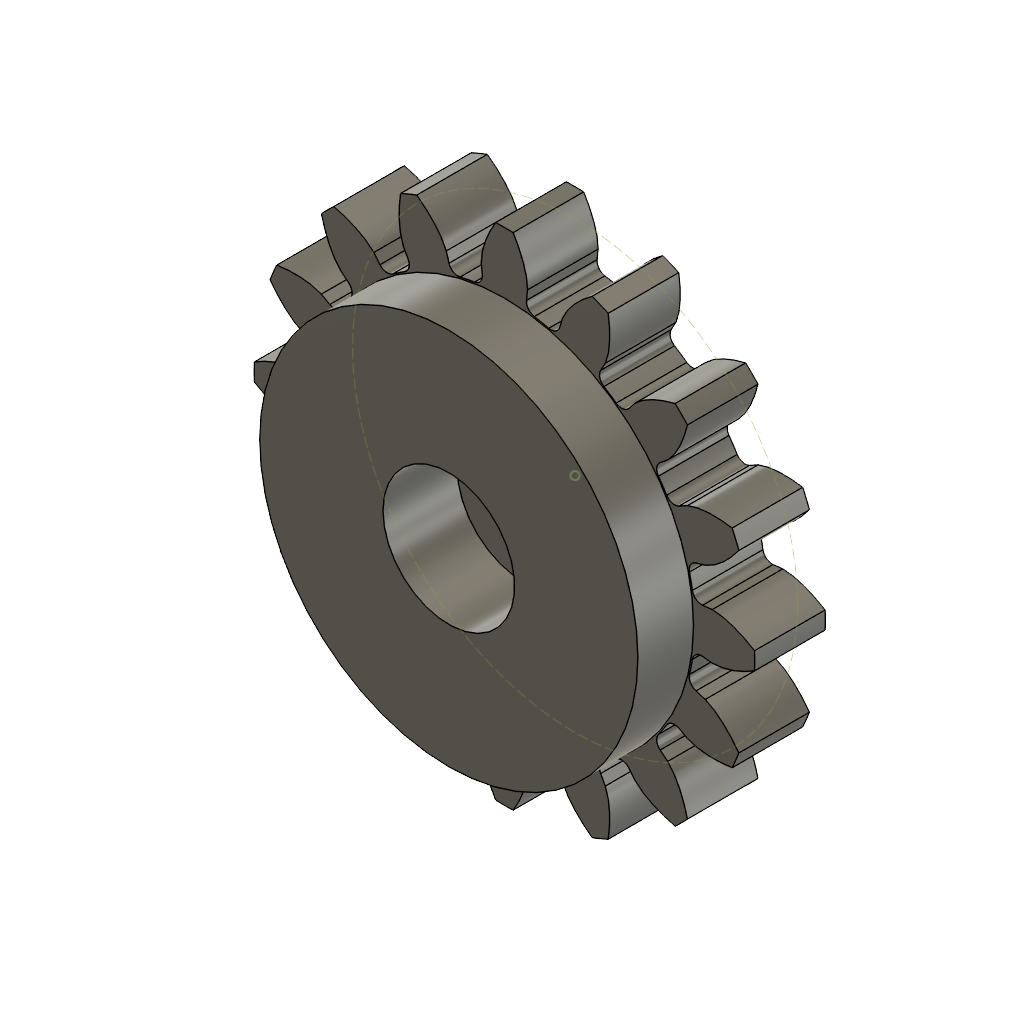
SpurGear (Autodesk Fusion 360 design; units mm, degrees)
part number: 2026-10-06-11-43-39-479
Autodesk Fusion 360 part; units mm, degrees
(part 1 of 6)
sketch "スケッチ1" plane through (0, 0, 0) normal (0, 0, 1) x (1, 0, 0)
  circle A0 centre (0, 0) radius 10.2645
extrude "押し出し1" add sketch "スケッチ1" along normal blind 3.81
sketch "スケッチ2" plane through (0, 0, 0) normal (0, 0, 1) x (1, 0, 0)
  spline S0 degree 5 poles (11.2069, -1.2491) (11.2134, -1.2498) (11.2264, -1.251) (11.246, -1.2524) (11.2721, -1.2531) (11.3048, -1.2525) (11.3376, -1.2509) (11.3704, -1.2487) (11.4033, -1.2461) (11.4361, -1.2432) (11.469, -1.2401) (11.502, -1.2367) (11.5349, -1.2328) (11.5679, -1.2284) (11.6008, -1.2235) (11.6338, -1.2181) (11.6668, -1.2124) (11.6998, -1.2062) (11.7328, -1.1998) (11.7659, -1.1931) (11.7989, -1.1861) (11.8319, -1.1788) (11.8649, -1.1712) (11.8979, -1.1632) (11.9309, -1.155) (11.9639, -1.1464) (11.9969, -1.1375) (12.0299, -1.1284) (12.0629, -1.119) (12.0958, -1.1093) (12.1288, -1.0993) (12.1617, -1.0891) (12.1947, -1.0787) (12.2276, -1.0679) (12.2605, -1.0569) (12.2934, -1.0457) (12.3262, -1.0342) (12.3591, -1.0224) (12.3919, -1.0105) (12.4247, -0.9982) (12.4575, -0.9858) (12.4903, -0.973) (12.5231, -0.9601) (12.5558, -0.9469) (12.5885, -0.9335) (12.6212, -0.9199) (12.6539, -0.906) (12.6865, -0.8919) (12.7191, -0.8776) (12.7517, -0.8631) (12.7842, -0.8483) (12.8167, -0.8334) (12.8492, -0.8182) (12.8817, -0.8028) (12.9141, -0.7872) (12.9465, -0.7713) (12.9789, -0.7553) (13.0112, -0.7391) (13.0435, -0.7226) (13.0758, -0.7059) (13.108, -0.6891) (13.1402, -0.672) (13.1724, -0.6547) (13.2045, -0.6373) (13.2366, -0.6196) (13.2686, -0.6017) (13.3006, -0.5836) (13.3326, -0.5654) (13.3645, -0.5469) (13.3964, -0.5282) (13.4282, -0.5094) (13.4537, -0.4942) (13.4727, -0.4826) (13.4854, -0.4749) (13.4918, -0.4711) knots 0 0 0 0 0 0 0.01428571 0.02857143 0.04285714 0.05714286 0.07142857 0.08571429 0.1 0.11428571 0.12857143 0.14285714 0.15714286 0.17142857 0.18571429 0.2 0.21428571 0.22857143 0.24285714 0.25714286 0.27142857 0.28571429 0.3 0.31428571 0.32857143 0.34285714 0.35714286 0.37142857 0.38571429 0.4 0.41428571 0.42857143 0.44285714 0.45714286 0.47142857 0.48571429 0.5 0.51428571 0.52857143 0.54285714 0.55714286 0.57142857 0.58571429 0.6 0.61428571 0.62857143 0.64285714 0.65714286 0.67142857 0.68571429 0.7 0.71428571 0.72857143 0.74285714 0.75714286 0.77142857 0.78571429 0.8 0.81428571 0.82857143 0.84285714 0.85714286 0.87142857 0.88571429 0.9 0.91428571 0.92857143 0.94285714 0.95714286 0.97142857 0.98571429 1 1 1 1 1 1
  spline S1 degree 5 poles (11.2069, 1.2491) (11.2134, 1.2498) (11.2264, 1.251) (11.246, 1.2524) (11.2721, 1.2531) (11.3048, 1.2525) (11.3376, 1.2509) (11.3704, 1.2487) (11.4033, 1.2461) (11.4361, 1.2432) (11.469, 1.2401) (11.502, 1.2367) (11.5349, 1.2328) (11.5679, 1.2284) (11.6008, 1.2235) (11.6338, 1.2181) (11.6668, 1.2124) (11.6998, 1.2062) (11.7328, 1.1998) (11.7659, 1.1931) (11.7989, 1.1861) (11.8319, 1.1788) (11.8649, 1.1712) (11.8979, 1.1632) (11.9309, 1.155) (11.9639, 1.1464) (11.9969, 1.1375) (12.0299, 1.1284) (12.0629, 1.119) (12.0958, 1.1093) (12.1288, 1.0993) (12.1617, 1.0891) (12.1947, 1.0787) (12.2276, 1.0679) (12.2605, 1.0569) (12.2934, 1.0457) (12.3262, 1.0342) (12.3591, 1.0224) (12.3919, 1.0105) (12.4247, 0.9982) (12.4575, 0.9858) (12.4903, 0.973) (12.5231, 0.9601) (12.5558, 0.9469) (12.5885, 0.9335) (12.6212, 0.9199) (12.6539, 0.906) (12.6865, 0.8919) (12.7191, 0.8776) (12.7517, 0.8631) (12.7842, 0.8483) (12.8167, 0.8334) (12.8492, 0.8182) (12.8817, 0.8028) (12.9141, 0.7872) (12.9465, 0.7713) (12.9789, 0.7553) (13.0112, 0.7391) (13.0435, 0.7226) (13.0758, 0.7059) (13.108, 0.6891) (13.1402, 0.672) (13.1724, 0.6547) (13.2045, 0.6373) (13.2366, 0.6196) (13.2686, 0.6017) (13.3006, 0.5836) (13.3326, 0.5654) (13.3645, 0.5469) (13.3964, 0.5282) (13.4282, 0.5094) (13.4537, 0.4942) (13.4727, 0.4826) (13.4854, 0.4749) (13.4918, 0.4711) knots 0 0 0 0 0 0 0.01428571 0.02857143 0.04285714 0.05714286 0.07142857 0.08571429 0.1 0.11428571 0.12857143 0.14285714 0.15714286 0.17142857 0.18571429 0.2 0.21428571 0.22857143 0.24285714 0.25714286 0.27142857 0.28571429 0.3 0.31428571 0.32857143 0.34285714 0.35714286 0.37142857 0.38571429 0.4 0.41428571 0.42857143 0.44285714 0.45714286 0.47142857 0.48571429 0.5 0.51428571 0.52857143 0.54285714 0.55714286 0.57142857 0.58571429 0.6 0.61428571 0.62857143 0.64285714 0.65714286 0.67142857 0.68571429 0.7 0.71428571 0.72857143 0.74285714 0.75714286 0.77142857 0.78571429 0.8 0.81428571 0.82857143 0.84285714 0.85714286 0.87142857 0.88571429 0.9 0.91428571 0.92857143 0.94285714 0.95714286 0.97142857 0.98571429 1 1 1 1 1 1
  arc A0 (13.4918, -0.4711) -> (13.4918, 0.4711) centre (0, 0) ccw
  line L0 (10.1914, -1.1359) -> (11.2069, -1.2491)
  line L1 (10.1914, 1.1359) -> (11.2069, 1.2491)
  line L2 (10.1914, -1.1359) -> (10.1914, 1.1359)
  point P0 (11.3667, -1.2488)
  point P1 (11.5282, -1.2335)
  point P2 (11.6906, -1.2079)
  point P3 (11.8537, -1.1737)
  point P4 (12.0173, -1.1318)
  point P5 (12.1813, -1.0829)
  point P6 (12.3455, -1.0273)
  point P7 (12.5098, -0.9653)
  point P8 (12.6741, -0.8972)
  point P9 (12.8383, -0.8233)
  point P10 (13.0023, -0.7435)
  point P11 (13.1659, -0.6582)
  point P12 (13.3291, -0.5673)
  point P13 (11.3667, 1.2488)
  point P14 (11.5282, 1.2335)
  point P15 (11.6906, 1.2079)
  point P16 (11.8537, 1.1737)
  point P17 (12.0173, 1.1318)
  point P18 (12.1813, 1.0829)
  point P19 (12.3455, 1.0273)
  point P20 (12.5098, 0.9653)
  point P21 (12.6741, 0.8972)
  point P22 (12.8383, 0.8233)
  point P23 (13.0023, 0.7435)
  point P24 (13.1659, 0.6582)
  point P25 (13.3291, 0.5673)
extrude "押し出し2" add sketch "スケッチ2" along normal blind 3.81
fillet "フィレット1" radius 0.5 2 edges at (10.2013, -1.137, 1.905) (10.2013, 1.137, 1.905)
pattern_circular "C パターン1" count 16 over 360 about axis through (0, 0, 0) along (0, 0, 1) of "押し出し2", "フィレット1"
sketch "スケッチ3" plane through (0, 0, 0) normal (0, 0, 1) x (1, 0, 0)
  circle A0 centre (0, 0) radius 12 construction
sketch "スケッチ4" plane through (0, 0, 3.81) normal (0, 0, 1) x (1, 0, 0)
  arc A0 (9.9818, -2.3924) -> (10.1375, -1.6096) centre (0, 0) ccw
  arc A1 (10.6867, -1.1911) -> (10.1375, -1.6096) centre (10.6313, -1.688) ccw
  line L0 (10.6867, -1.1911) -> (11.2069, -1.2491)
  spline S0 degree 5 poles (11.2069, -1.2491) (11.2134, -1.2498) (11.2264, -1.251) (11.246, -1.2524) (11.2721, -1.2531) (11.3048, -1.2525) (11.3376, -1.2509) (11.3704, -1.2487) (11.4033, -1.2461) (11.4361, -1.2432) (11.469, -1.2401) (11.502, -1.2367) (11.5349, -1.2328) (11.5679, -1.2284) (11.6008, -1.2235) (11.6338, -1.2181) (11.6668, -1.2124) (11.6998, -1.2062) (11.7328, -1.1998) (11.7659, -1.1931) (11.7989, -1.1861) (11.8319, -1.1788) (11.8649, -1.1712) (11.8979, -1.1632) (11.9309, -1.155) (11.9639, -1.1464) (11.9969, -1.1375) (12.0299, -1.1284) (12.0629, -1.119) (12.0958, -1.1093) (12.1288, -1.0993) (12.1617, -1.0891) (12.1947, -1.0787) (12.2276, -1.0679) (12.2605, -1.0569) (12.2934, -1.0457) (12.3262, -1.0342) (12.3591, -1.0224) (12.3919, -1.0105) (12.4247, -0.9982) (12.4575, -0.9858) (12.4903, -0.973) (12.5231, -0.9601) (12.5558, -0.9469) (12.5885, -0.9335) (12.6212, -0.9199) (12.6539, -0.906) (12.6865, -0.8919) (12.7191, -0.8776) (12.7517, -0.8631) (12.7842, -0.8483) (12.8167, -0.8334) (12.8492, -0.8182) (12.8817, -0.8028) (12.9141, -0.7872) (12.9465, -0.7713) (12.9789, -0.7553) (13.0112, -0.7391) (13.0435, -0.7226) (13.0758, -0.7059) (13.108, -0.6891) (13.1402, -0.672) (13.1724, -0.6547) (13.2045, -0.6373) (13.2366, -0.6196) (13.2686, -0.6017) (13.3006, -0.5836) (13.3326, -0.5654) (13.3645, -0.5469) (13.3964, -0.5282) (13.4282, -0.5094) (13.4537, -0.4942) (13.4727, -0.4826) (13.4854, -0.4749) (13.4918, -0.4711) knots 0 0 0 0 0 0 0.01428571 0.02857143 0.04285714 0.05714286 0.07142857 0.08571429 0.1 0.11428571 0.12857143 0.14285714 0.15714286 0.17142857 0.18571429 0.2 0.21428571 0.22857143 0.24285714 0.25714286 0.27142857 0.28571429 0.3 0.31428571 0.32857143 0.34285714 0.35714286 0.37142857 0.38571429 0.4 0.41428571 0.42857143 0.44285714 0.45714286 0.47142857 0.48571429 0.5 0.51428571 0.52857143 0.54285714 0.55714286 0.57142857 0.58571429 0.6 0.61428571 0.62857143 0.64285714 0.65714286 0.67142857 0.68571429 0.7 0.71428571 0.72857143 0.74285714 0.75714286 0.77142857 0.78571429 0.8 0.81428571 0.82857143 0.84285714 0.85714286 0.87142857 0.88571429 0.9 0.91428571 0.92857143 0.94285714 0.95714286 0.97142857 0.98571429 1 1 1 1 1 1
  arc A2 (13.4918, -0.4711) -> (13.4918, 0.4711) centre (0, 0) ccw
  spline S1 degree 5 poles (13.4918, 0.4711) (13.4854, 0.4749) (13.4727, 0.4826) (13.4537, 0.4942) (13.4282, 0.5094) (13.3964, 0.5282) (13.3645, 0.5469) (13.3326, 0.5654) (13.3006, 0.5836) (13.2686, 0.6017) (13.2366, 0.6196) (13.2045, 0.6373) (13.1724, 0.6547) (13.1402, 0.672) (13.108, 0.6891) (13.0758, 0.7059) (13.0435, 0.7226) (13.0112, 0.7391) (12.9789, 0.7553) (12.9465, 0.7713) (12.9141, 0.7872) (12.8817, 0.8028) (12.8492, 0.8182) (12.8167, 0.8334) (12.7842, 0.8483) (12.7517, 0.8631) (12.7191, 0.8776) (12.6865, 0.8919) (12.6539, 0.906) (12.6212, 0.9199) (12.5885, 0.9335) (12.5558, 0.9469) (12.5231, 0.9601) (12.4903, 0.973) (12.4575, 0.9858) (12.4247, 0.9982) (12.3919, 1.0105) (12.3591, 1.0224) (12.3262, 1.0342) (12.2934, 1.0457) (12.2605, 1.0569) (12.2276, 1.0679) (12.1947, 1.0787) (12.1617, 1.0891) (12.1288, 1.0993) (12.0958, 1.1093) (12.0629, 1.119) (12.0299, 1.1284) (11.9969, 1.1375) (11.9639, 1.1464) (11.9309, 1.155) (11.8979, 1.1632) (11.8649, 1.1712) (11.8319, 1.1788) (11.7989, 1.1861) (11.7659, 1.1931) (11.7328, 1.1998) (11.6998, 1.2062) (11.6668, 1.2124) (11.6338, 1.2181) (11.6008, 1.2235) (11.5679, 1.2284) (11.5349, 1.2328) (11.502, 1.2367) (11.469, 1.2401) (11.4361, 1.2432) (11.4033, 1.2461) (11.3704, 1.2487) (11.3376, 1.2509) (11.3048, 1.2525) (11.2721, 1.2531) (11.246, 1.2524) (11.2264, 1.251) (11.2134, 1.2498) (11.2069, 1.2491) knots -1 -1 -1 -1 -1 -1 -0.98571429 -0.97142857 -0.95714286 -0.94285714 -0.92857143 -0.91428571 -0.9 -0.88571429 -0.87142857 -0.85714286 -0.84285714 -0.82857143 -0.81428571 -0.8 -0.78571429 -0.77142857 -0.75714286 -0.74285714 -0.72857143 -0.71428571 -0.7 -0.68571429 -0.67142857 -0.65714286 -0.64285714 -0.62857143 -0.61428571 -0.6 -0.58571429 -0.57142857 -0.55714286 -0.54285714 -0.52857143 -0.51428571 -0.5 -0.48571429 -0.47142857 -0.45714286 -0.44285714 -0.42857143 -0.41428571 -0.4 -0.38571429 -0.37142857 -0.35714286 -0.34285714 -0.32857143 -0.31428571 -0.3 -0.28571429 -0.27142857 -0.25714286 -0.24285714 -0.22857143 -0.21428571 -0.2 -0.18571429 -0.17142857 -0.15714286 -0.14285714 -0.12857143 -0.11428571 -0.1 -0.08571429 -0.07142857 -0.05714286 -0.04285714 -0.02857143 -0.01428571 0 0 0 0 0 0
  line L1 (11.2069, 1.2491) -> (10.6867, 1.1911)
  arc A3 (10.1375, 1.6096) -> (10.6867, 1.1911) centre (10.6313, 1.688) ccw
  arc A4 (10.1375, 1.6096) -> (9.9818, 2.3924) centre (0, 0) ccw
  arc A5 (10.329, 2.9892) -> (9.9818, 2.3924) centre (10.468, 2.5089) ccw
  line L2 (10.329, 2.9892) -> (10.8318, 3.1347)
  spline S2 degree 5 poles (10.8318, 3.1347) (10.8381, 3.1365) (10.8506, 3.1404) (10.8692, 3.1466) (10.8936, 3.1559) (10.9236, 3.169) (10.9533, 3.183) (10.9827, 3.1976) (11.0121, 3.2126) (11.0414, 3.2279) (11.0706, 3.2433) (11.0997, 3.2591) (11.1286, 3.2753) (11.1574, 3.2919) (11.186, 3.3091) (11.2144, 3.3267) (11.2427, 3.3446) (11.2708, 3.3629) (11.2989, 3.3815) (11.3268, 3.4003) (11.3546, 3.4194) (11.3823, 3.4388) (11.4099, 3.4585) (11.4374, 3.4784) (11.4647, 3.4987) (11.4919, 3.5193) (11.519, 3.5401) (11.546, 3.5611) (11.5728, 3.5825) (11.5996, 3.604) (11.6262, 3.6258) (11.6528, 3.6479) (11.6792, 3.6701) (11.7055, 3.6926) (11.7317, 3.7154) (11.7578, 3.7384) (11.7837, 3.7616) (11.8096, 3.785) (11.8353, 3.8086) (11.861, 3.8325) (11.8865, 3.8566) (11.9119, 3.8809) (11.9372, 3.9054) (11.9624, 3.93) (11.9875, 3.955) (12.0125, 3.9801) (12.0374, 4.0054) (12.0621, 4.0309) (12.0868, 4.0566) (12.1113, 4.0825) (12.1357, 4.1085) (12.16, 4.1348) (12.1843, 4.1613) (12.2083, 4.1879) (12.2323, 4.2148) (12.2562, 4.2418) (12.28, 4.269) (12.3036, 4.2964) (12.3272, 4.3239) (12.3506, 4.3517) (12.3739, 4.3796) (12.3971, 4.4077) (12.4202, 4.4359) (12.4432, 4.4644) (12.4661, 4.493) (12.4889, 4.5218) (12.5115, 4.5507) (12.5341, 4.5798) (12.5565, 4.6091) (12.5788, 4.6385) (12.601, 4.6681) (12.6187, 4.692) (12.6319, 4.7099) (12.6407, 4.7219) (12.645, 4.7279) knots 0 0 0 0 0 0 0.01428571 0.02857143 0.04285714 0.05714286 0.07142857 0.08571429 0.1 0.11428571 0.12857143 0.14285714 0.15714286 0.17142857 0.18571429 0.2 0.21428571 0.22857143 0.24285714 0.25714286 0.27142857 0.28571429 0.3 0.31428571 0.32857143 0.34285714 0.35714286 0.37142857 0.38571429 0.4 0.41428571 0.42857143 0.44285714 0.45714286 0.47142857 0.48571429 0.5 0.51428571 0.52857143 0.54285714 0.55714286 0.57142857 0.58571429 0.6 0.61428571 0.62857143 0.64285714 0.65714286 0.67142857 0.68571429 0.7 0.71428571 0.72857143 0.74285714 0.75714286 0.77142857 0.78571429 0.8 0.81428571 0.82857143 0.84285714 0.85714286 0.87142857 0.88571429 0.9 0.91428571 0.92857143 0.94285714 0.95714286 0.97142857 0.98571429 1 1 1 1 1 1
  arc A6 (12.645, 4.7279) -> (12.2845, 5.5983) centre (0, 0) ccw
  spline S3 degree 5 poles (12.2845, 5.5983) (12.2772, 5.5994) (12.2625, 5.6017) (12.2405, 5.605) (12.2111, 5.6094) (12.1745, 5.6146) (12.1379, 5.6197) (12.1013, 5.6245) (12.0648, 5.6291) (12.0283, 5.6336) (11.9919, 5.6378) (11.9555, 5.6419) (11.9191, 5.6457) (11.8828, 5.6494) (11.8465, 5.6529) (11.8103, 5.6561) (11.7741, 5.6591) (11.738, 5.662) (11.7019, 5.6646) (11.6659, 5.6671) (11.6299, 5.6693) (11.5939, 5.6713) (11.558, 5.6731) (11.5222, 5.6747) (11.4864, 5.6761) (11.4507, 5.6772) (11.4151, 5.6782) (11.3795, 5.6789) (11.3439, 5.6795) (11.3084, 5.6798) (11.273, 5.6799) (11.2377, 5.6797) (11.2024, 5.6794) (11.1672, 5.6788) (11.132, 5.678) (11.097, 5.677) (11.062, 5.6757) (11.027, 5.6742) (10.9922, 5.6725) (10.9574, 5.6706) (10.9227, 5.6684) (10.8881, 5.6659) (10.8536, 5.6633) (10.8192, 5.6603) (10.7848, 5.6571) (10.7506, 5.6537) (10.7164, 5.6501) (10.6823, 5.6461) (10.6484, 5.642) (10.6145, 5.6375) (10.5807, 5.6328) (10.5471, 5.6278) (10.5135, 5.6225) (10.4801, 5.6169) (10.4468, 5.611) (10.4137, 5.6049) (10.3806, 5.5984) (10.3476, 5.5917) (10.3148, 5.5848) (10.2821, 5.5775) (10.2496, 5.5698) (10.2172, 5.5617) (10.1851, 5.5532) (10.1532, 5.5441) (10.1215, 5.5347) (10.0899, 5.525) (10.0584, 5.515) (10.027, 5.5049) (9.9958, 5.4944) (9.9649, 5.4833) (9.9345, 5.4713) (9.9106, 5.4607) (9.8931, 5.452) (9.8816, 5.4458) (9.8759, 5.4427) knots -1 -1 -1 -1 -1 -1 -0.98571429 -0.97142857 -0.95714286 -0.94285714 -0.92857143 -0.91428571 -0.9 -0.88571429 -0.87142857 -0.85714286 -0.84285714 -0.82857143 -0.81428571 -0.8 -0.78571429 -0.77142857 -0.75714286 -0.74285714 -0.72857143 -0.71428571 -0.7 -0.68571429 -0.67142857 -0.65714286 -0.64285714 -0.62857143 -0.61428571 -0.6 -0.58571429 -0.57142857 -0.55714286 -0.54285714 -0.52857143 -0.51428571 -0.5 -0.48571429 -0.47142857 -0.45714286 -0.44285714 -0.42857143 -0.41428571 -0.4 -0.38571429 -0.37142857 -0.35714286 -0.34285714 -0.32857143 -0.31428571 -0.3 -0.28571429 -0.27142857 -0.25714286 -0.24285714 -0.22857143 -0.21428571 -0.2 -0.18571429 -0.17142857 -0.15714286 -0.14285714 -0.12857143 -0.11428571 -0.1 -0.08571429 -0.07142857 -0.05714286 -0.04285714 -0.02857143 -0.01428571 0 0 0 0 0 0
  line L3 (9.8759, 5.4427) -> (9.4174, 5.19)
  arc A7 (8.7499, 5.3665) -> (9.4174, 5.19) centre (9.1761, 5.6279) ccw
  arc A8 (8.7499, 5.3665) -> (8.3065, 6.0302) centre (0, 0) ccw
  arc A9 (8.3989, 6.7144) -> (8.3065, 6.0302) centre (8.7111, 6.3239) ccw
  line L4 (8.3989, 6.7144) -> (8.8077, 7.0413)
  spline S4 degree 5 poles (8.8077, 7.0413) (8.8128, 7.0454) (8.8229, 7.0537) (8.8377, 7.0665) (8.8566, 7.0845) (8.8794, 7.108) (8.9014, 7.1323) (8.923, 7.1571) (8.9444, 7.1822) (8.9656, 7.2075) (8.9867, 7.233) (9.0076, 7.2587) (9.0281, 7.2847) (9.0483, 7.3111) (9.0682, 7.3379) (9.0877, 7.365) (9.107, 7.3924) (9.126, 7.4201) (9.1448, 7.448) (9.1634, 7.4761) (9.1817, 7.5044) (9.1999, 7.5329) (9.2179, 7.5616) (9.2356, 7.5906) (9.2531, 7.6197) (9.2704, 7.6491) (9.2874, 7.6787) (9.3043, 7.7085) (9.321, 7.7385) (9.3374, 7.7687) (9.3537, 7.799) (9.3698, 7.8295) (9.3857, 7.8602) (9.4013, 7.8911) (9.4168, 7.9221) (9.4321, 7.9533) (9.4473, 7.9847) (9.4622, 8.0162) (9.4769, 8.0479) (9.4915, 8.0798) (9.5058, 8.1118) (9.52, 8.1439) (9.534, 8.1763) (9.5479, 8.2087) (9.5615, 8.2413) (9.575, 8.2741) (9.5883, 8.307) (9.6014, 8.34) (9.6143, 8.3732) (9.6271, 8.4065) (9.6397, 8.4399) (9.6521, 8.4735) (9.6643, 8.5072) (9.6764, 8.5411) (9.6883, 8.5751) (9.7, 8.6092) (9.7115, 8.6434) (9.7229, 8.6777) (9.7341, 8.7122) (9.7452, 8.7468) (9.756, 8.7815) (9.7667, 8.8164) (9.7772, 8.8513) (9.7876, 8.8864) (9.7978, 8.9216) (9.8078, 8.9569) (9.8177, 8.9923) (9.8273, 9.0278) (9.8369, 9.0634) (9.8462, 9.0992) (9.8554, 9.135) (9.8626, 9.1638) (9.8679, 9.1854) (9.8715, 9.1998) (9.8732, 9.207) knots 0 0 0 0 0 0 0.01428571 0.02857143 0.04285714 0.05714286 0.07142857 0.08571429 0.1 0.11428571 0.12857143 0.14285714 0.15714286 0.17142857 0.18571429 0.2 0.21428571 0.22857143 0.24285714 0.25714286 0.27142857 0.28571429 0.3 0.31428571 0.32857143 0.34285714 0.35714286 0.37142857 0.38571429 0.4 0.41428571 0.42857143 0.44285714 0.45714286 0.47142857 0.48571429 0.5 0.51428571 0.52857143 0.54285714 0.55714286 0.57142857 0.58571429 0.6 0.61428571 0.62857143 0.64285714 0.65714286 0.67142857 0.68571429 0.7 0.71428571 0.72857143 0.74285714 0.75714286 0.77142857 0.78571429 0.8 0.81428571 0.82857143 0.84285714 0.85714286 0.87142857 0.88571429 0.9 0.91428571 0.92857143 0.94285714 0.95714286 0.97142857 0.98571429 1 1 1 1 1 1
  arc A10 (9.8732, 9.207) -> (9.207, 9.8732) centre (0, 0) ccw
  spline S5 degree 5 poles (9.207, 9.8732) (9.1998, 9.8715) (9.1854, 9.8679) (9.1638, 9.8626) (9.135, 9.8554) (9.0992, 9.8462) (9.0634, 9.8369) (9.0278, 9.8273) (8.9923, 9.8177) (8.9569, 9.8078) (8.9216, 9.7978) (8.8864, 9.7876) (8.8513, 9.7772) (8.8164, 9.7667) (8.7815, 9.756) (8.7468, 9.7452) (8.7122, 9.7341) (8.6777, 9.7229) (8.6434, 9.7115) (8.6092, 9.7) (8.5751, 9.6883) (8.5411, 9.6764) (8.5072, 9.6643) (8.4735, 9.6521) (8.4399, 9.6397) (8.4065, 9.6271) (8.3732, 9.6143) (8.34, 9.6014) (8.307, 9.5883) (8.2741, 9.575) (8.2413, 9.5615) (8.2087, 9.5479) (8.1763, 9.534) (8.1439, 9.52) (8.1118, 9.5058) (8.0798, 9.4915) (8.0479, 9.4769) (8.0162, 9.4622) (7.9847, 9.4473) (7.9533, 9.4321) (7.9221, 9.4168) (7.8911, 9.4013) (7.8602, 9.3857) (7.8295, 9.3698) (7.799, 9.3537) (7.7687, 9.3374) (7.7385, 9.321) (7.7085, 9.3043) (7.6787, 9.2874) (7.6491, 9.2704) (7.6197, 9.2531) (7.5906, 9.2356) (7.5616, 9.2179) (7.5329, 9.1999) (7.5044, 9.1817) (7.4761, 9.1634) (7.448, 9.1448) (7.4201, 9.126) (7.3924, 9.107) (7.365, 9.0877) (7.3379, 9.0682) (7.3111, 9.0483) (7.2847, 9.0281) (7.2587, 9.0076) (7.233, 8.9867) (7.2075, 8.9656) (7.1822, 8.9444) (7.1571, 8.923) (7.1323, 8.9014) (7.108, 8.8794) (7.0845, 8.8566) (7.0665, 8.8377) (7.0537, 8.8229) (7.0454, 8.8128) (7.0413, 8.8077) knots -1 -1 -1 -1 -1 -1 -0.98571429 -0.97142857 -0.95714286 -0.94285714 -0.92857143 -0.91428571 -0.9 -0.88571429 -0.87142857 -0.85714286 -0.84285714 -0.82857143 -0.81428571 -0.8 -0.78571429 -0.77142857 -0.75714286 -0.74285714 -0.72857143 -0.71428571 -0.7 -0.68571429 -0.67142857 -0.65714286 -0.64285714 -0.62857143 -0.61428571 -0.6 -0.58571429 -0.57142857 -0.55714286 -0.54285714 -0.52857143 -0.51428571 -0.5 -0.48571429 -0.47142857 -0.45714286 -0.44285714 -0.42857143 -0.41428571 -0.4 -0.38571429 -0.37142857 -0.35714286 -0.34285714 -0.32857143 -0.31428571 -0.3 -0.28571429 -0.27142857 -0.25714286 -0.24285714 -0.22857143 -0.21428571 -0.2 -0.18571429 -0.17142857 -0.15714286 -0.14285714 -0.12857143 -0.11428571 -0.1 -0.08571429 -0.07142857 -0.05714286 -0.04285714 -0.02857143 -0.01428571 0 0 0 0 0 0
  line L5 (7.0413, 8.8077) -> (6.7144, 8.3989)
  arc A11 (6.0302, 8.3065) -> (6.7144, 8.3989) centre (6.3239, 8.7111) ccw
  arc A12 (6.0302, 8.3065) -> (5.3665, 8.7499) centre (0, 0) ccw
  arc A13 (5.19, 9.4174) -> (5.3665, 8.7499) centre (5.6279, 9.1761) ccw
  line L6 (5.19, 9.4174) -> (5.4427, 9.8759)
  spline S6 degree 5 poles (5.4427, 9.8759) (5.4458, 9.8816) (5.452, 9.8931) (5.4607, 9.9106) (5.4713, 9.9345) (5.4833, 9.9649) (5.4944, 9.9958) (5.5049, 10.027) (5.515, 10.0584) (5.525, 10.0899) (5.5347, 10.1215) (5.5441, 10.1532) (5.5532, 10.1851) (5.5617, 10.2172) (5.5698, 10.2496) (5.5775, 10.2821) (5.5848, 10.3148) (5.5917, 10.3476) (5.5984, 10.3806) (5.6049, 10.4137) (5.611, 10.4468) (5.6169, 10.4801) (5.6225, 10.5135) (5.6278, 10.5471) (5.6328, 10.5807) (5.6375, 10.6145) (5.642, 10.6484) (5.6461, 10.6823) (5.6501, 10.7164) (5.6537, 10.7506) (5.6571, 10.7848) (5.6603, 10.8192) (5.6633, 10.8536) (5.6659, 10.8881) (5.6684, 10.9227) (5.6706, 10.9574) (5.6725, 10.9922) (5.6742, 11.027) (5.6757, 11.062) (5.677, 11.097) (5.678, 11.132) (5.6788, 11.1672) (5.6794, 11.2024) (5.6797, 11.2377) (5.6799, 11.273) (5.6798, 11.3084) (5.6795, 11.3439) (5.6789, 11.3795) (5.6782, 11.4151) (5.6772, 11.4507) (5.6761, 11.4864) (5.6747, 11.5222) (5.6731, 11.558) (5.6713, 11.5939) (5.6693, 11.6299) (5.6671, 11.6659) (5.6646, 11.7019) (5.662, 11.738) (5.6591, 11.7741) (5.6561, 11.8103) (5.6529, 11.8465) (5.6494, 11.8828) (5.6457, 11.9191) (5.6419, 11.9555) (5.6378, 11.9919) (5.6336, 12.0283) (5.6291, 12.0648) (5.6245, 12.1013) (5.6197, 12.1379) (5.6146, 12.1745) (5.6094, 12.2111) (5.605, 12.2405) (5.6017, 12.2625) (5.5994, 12.2772) (5.5983, 12.2845) knots 0 0 0 0 0 0 0.01428571 0.02857143 0.04285714 0.05714286 0.07142857 0.08571429 0.1 0.11428571 0.12857143 0.14285714 0.15714286 0.17142857 0.18571429 0.2 0.21428571 0.22857143 0.24285714 0.25714286 0.27142857 0.28571429 0.3 0.31428571 0.32857143 0.34285714 0.35714286 0.37142857 0.38571429 0.4 0.41428571 0.42857143 0.44285714 0.45714286 0.47142857 0.48571429 0.5 0.51428571 0.52857143 0.54285714 0.55714286 0.57142857 0.58571429 0.6 0.61428571 0.62857143 0.64285714 0.65714286 0.67142857 0.68571429 0.7 0.71428571 0.72857143 0.74285714 0.75714286 0.77142857 0.78571429 0.8 0.81428571 0.82857143 0.84285714 0.85714286 0.87142857 0.88571429 0.9 0.91428571 0.92857143 0.94285714 0.95714286 0.97142857 0.98571429 1 1 1 1 1 1
  arc A14 (5.5983, 12.2845) -> (4.7279, 12.645) centre (0, 0) ccw
  spline S7 degree 5 poles (4.7279, 12.645) (4.7219, 12.6407) (4.7099, 12.6319) (4.692, 12.6187) (4.6681, 12.601) (4.6385, 12.5788) (4.6091, 12.5565) (4.5798, 12.5341) (4.5507, 12.5115) (4.5218, 12.4889) (4.493, 12.4661) (4.4644, 12.4432) (4.4359, 12.4202) (4.4077, 12.3971) (4.3796, 12.3739) (4.3517, 12.3506) (4.3239, 12.3272) (4.2964, 12.3036) (4.269, 12.28) (4.2418, 12.2562) (4.2148, 12.2323) (4.1879, 12.2083) (4.1613, 12.1843) (4.1348, 12.16) (4.1085, 12.1357) (4.0825, 12.1113) (4.0566, 12.0868) (4.0309, 12.0621) (4.0054, 12.0374) (3.9801, 12.0125) (3.955, 11.9875) (3.93, 11.9624) (3.9054, 11.9372) (3.8809, 11.9119) (3.8566, 11.8865) (3.8325, 11.861) (3.8086, 11.8353) (3.785, 11.8096) (3.7616, 11.7837) (3.7384, 11.7578) (3.7154, 11.7317) (3.6926, 11.7055) (3.6701, 11.6792) (3.6479, 11.6528) (3.6258, 11.6262) (3.604, 11.5996) (3.5825, 11.5728) (3.5611, 11.546) (3.5401, 11.519) (3.5193, 11.4919) (3.4987, 11.4647) (3.4784, 11.4374) (3.4585, 11.4099) (3.4388, 11.3823) (3.4194, 11.3546) (3.4003, 11.3268) (3.3815, 11.2989) (3.3629, 11.2708) (3.3446, 11.2427) (3.3267, 11.2144) (3.3091, 11.186) (3.2919, 11.1574) (3.2753, 11.1286) (3.2591, 11.0997) (3.2433, 11.0706) (3.2279, 11.0414) (3.2126, 11.0121) (3.1976, 10.9827) (3.183, 10.9533) (3.169, 10.9236) (3.1559, 10.8936) (3.1466, 10.8692) (3.1404, 10.8506) (3.1365, 10.8381) (3.1347, 10.8318) knots -1 -1 -1 -1 -1 -1 -0.98571429 -0.97142857 -0.95714286 -0.94285714 -0.92857143 -0.91428571 -0.9 -0.88571429 -0.87142857 -0.85714286 -0.84285714 -0.82857143 -0.81428571 -0.8 -0.78571429 -0.77142857 -0.75714286 -0.74285714 -0.72857143 -0.71428571 -0.7 -0.68571429 -0.67142857 -0.65714286 -0.64285714 -0.62857143 -0.61428571 -0.6 -0.58571429 -0.57142857 -0.55714286 -0.54285714 -0.52857143 -0.51428571 -0.5 -0.48571429 -0.47142857 -0.45714286 -0.44285714 -0.42857143 -0.41428571 -0.4 -0.38571429 -0.37142857 -0.35714286 -0.34285714 -0.32857143 -0.31428571 -0.3 -0.28571429 -0.27142857 -0.25714286 -0.24285714 -0.22857143 -0.21428571 -0.2 -0.18571429 -0.17142857 -0.15714286 -0.14285714 -0.12857143 -0.11428571 -0.1 -0.08571429 -0.07142857 -0.05714286 -0.04285714 -0.02857143 -0.01428571 0 0 0 0 0 0
  line L7 (3.1347, 10.8318) -> (2.9892, 10.329)
  arc A15 (2.3924, 9.9818) -> (2.9892, 10.329) centre (2.5089, 10.468) ccw
  arc A16 (2.3924, 9.9818) -> (1.6096, 10.1375) centre (0, 0) ccw
  arc A17 (1.1911, 10.6867) -> (1.6096, 10.1375) centre (1.688, 10.6313) ccw
  line L8 (1.1911, 10.6867) -> (1.2491, 11.2069)
  spline S8 degree 5 poles (1.2491, 11.2069) (1.2498, 11.2134) (1.251, 11.2264) (1.2524, 11.246) (1.2531, 11.2721) (1.2525, 11.3048) (1.2509, 11.3376) (1.2487, 11.3704) (1.2461, 11.4033) (1.2432, 11.4361) (1.2401, 11.469) (1.2367, 11.502) (1.2328, 11.5349) (1.2284, 11.5679) (1.2235, 11.6008) (1.2181, 11.6338) (1.2124, 11.6668) (1.2062, 11.6998) (1.1998, 11.7328) (1.1931, 11.7659) (1.1861, 11.7989) (1.1788, 11.8319) (1.1712, 11.8649) (1.1632, 11.8979) (1.155, 11.9309) (1.1464, 11.9639) (1.1375, 11.9969) (1.1284, 12.0299) (1.119, 12.0629) (1.1093, 12.0958) (1.0993, 12.1288) (1.0891, 12.1617) (1.0787, 12.1947) (1.0679, 12.2276) (1.0569, 12.2605) (1.0457, 12.2934) (1.0342, 12.3262) (1.0224, 12.3591) (1.0105, 12.3919) (0.9982, 12.4247) (0.9858, 12.4575) (0.973, 12.4903) (0.9601, 12.5231) (0.9469, 12.5558) (0.9335, 12.5885) (0.9199, 12.6212) (0.906, 12.6539) (0.8919, 12.6865) (0.8776, 12.7191) (0.8631, 12.7517) (0.8483, 12.7842) (0.8334, 12.8167) (0.8182, 12.8492) (0.8028, 12.8817) (0.7872, 12.9141) (0.7713, 12.9465) (0.7553, 12.9789) (0.7391, 13.0112) (0.7226, 13.0435) (0.7059, 13.0758) (0.6891, 13.108) (0.672, 13.1402) (0.6547, 13.1724) (0.6373, 13.2045) (0.6196, 13.2366) (0.6017, 13.2686) (0.5836, 13.3006) (0.5654, 13.3326) (0.5469, 13.3645) (0.5282, 13.3964) (0.5094, 13.4282) (0.4942, 13.4537) (0.4826, 13.4727) (0.4749, 13.4854) (0.4711, 13.4918) knots 0 0 0 0 0 0 0.01428571 0.02857143 0.04285714 0.05714286 0.07142857 0.08571429 0.1 0.11428571 0.12857143 0.14285714 0.15714286 0.17142857 0.18571429 0.2 0.21428571 0.22857143 0.24285714 0.25714286 0.27142857 0.28571429 0.3 0.31428571 0.32857143 0.34285714 0.35714286 0.37142857 0.38571429 0.4 0.41428571 0.42857143 0.44285714 0.45714286 0.47142857 0.48571429 0.5 0.51428571 0.52857143 0.54285714 0.55714286 0.57142857 0.58571429 0.6 0.61428571 0.62857143 0.64285714 0.65714286 0.67142857 0.68571429 0.7 0.71428571 0.72857143 0.74285714 0.75714286 0.77142857 0.78571429 0.8 0.81428571 0.82857143 0.84285714 0.85714286 0.87142857 0.88571429 0.9 0.91428571 0.92857143 0.94285714 0.95714286 0.97142857 0.98571429 1 1 1 1 1 1
  arc A18 (0.4711, 13.4918) -> (-0.4711, 13.4918) centre (0, 0) ccw
  spline S9 degree 5 poles (-0.4711, 13.4918) (-0.4749, 13.4854) (-0.4826, 13.4727) (-0.4942, 13.4537) (-0.5094, 13.4282) (-0.5282, 13.3964) (-0.5469, 13.3645) (-0.5654, 13.3326) (-0.5836, 13.3006) (-0.6017, 13.2686) (-0.6196, 13.2366) (-0.6373, 13.2045) (-0.6547, 13.1724) (-0.672, 13.1402) (-0.6891, 13.108) (-0.7059, 13.0758) (-0.7226, 13.0435) (-0.7391, 13.0112) (-0.7553, 12.9789) (-0.7713, 12.9465) (-0.7872, 12.9141) (-0.8028, 12.8817) (-0.8182, 12.8492) (-0.8334, 12.8167) (-0.8483, 12.7842) (-0.8631, 12.7517) (-0.8776, 12.7191) (-0.8919, 12.6865) (-0.906, 12.6539) (-0.9199, 12.6212) (-0.9335, 12.5885) (-0.9469, 12.5558) (-0.9601, 12.5231) (-0.973, 12.4903) (-0.9858, 12.4575) (-0.9982, 12.4247) (-1.0105, 12.3919) (-1.0224, 12.3591) (-1.0342, 12.3262) (-1.0457, 12.2934) (-1.0569, 12.2605) (-1.0679, 12.2276) (-1.0787, 12.1947) (-1.0891, 12.1617) (-1.0993, 12.1288) (-1.1093, 12.0958) (-1.119, 12.0629) (-1.1284, 12.0299) (-1.1375, 11.9969) (-1.1464, 11.9639) (-1.155, 11.9309) (-1.1632, 11.8979) (-1.1712, 11.8649) (-1.1788, 11.8319) (-1.1861, 11.7989) (-1.1931, 11.7659) (-1.1998, 11.7328) (-1.2062, 11.6998) (-1.2124, 11.6668) (-1.2181, 11.6338) (-1.2235, 11.6008) (-1.2284, 11.5679) (-1.2328, 11.5349) (-1.2367, 11.502) (-1.2401, 11.469) (-1.2432, 11.4361) (-1.2461, 11.4033) (-1.2487, 11.3704) (-1.2509, 11.3376) (-1.2525, 11.3048) (-1.2531, 11.2721) (-1.2524, 11.246) (-1.251, 11.2264) (-1.2498, 11.2134) (-1.2491, 11.2069) knots -1 -1 -1 -1 -1 -1 -0.98571429 -0.97142857 -0.95714286 -0.94285714 -0.92857143 -0.91428571 -0.9 -0.88571429 -0.87142857 -0.85714286 -0.84285714 -0.82857143 -0.81428571 -0.8 -0.78571429 -0.77142857 -0.75714286 -0.74285714 -0.72857143 -0.71428571 -0.7 -0.68571429 -0.67142857 -0.65714286 -0.64285714 -0.62857143 -0.61428571 -0.6 -0.58571429 -0.57142857 -0.55714286 -0.54285714 -0.52857143 -0.51428571 -0.5 -0.48571429 -0.47142857 -0.45714286 -0.44285714 -0.42857143 -0.41428571 -0.4 -0.38571429 -0.37142857 -0.35714286 -0.34285714 -0.32857143 -0.31428571 -0.3 -0.28571429 -0.27142857 -0.25714286 -0.24285714 -0.22857143 -0.21428571 -0.2 -0.18571429 -0.17142857 -0.15714286 -0.14285714 -0.12857143 -0.11428571 -0.1 -0.08571429 -0.07142857 -0.05714286 -0.04285714 -0.02857143 -0.01428571 0 0 0 0 0 0
  line L9 (-1.2491, 11.2069) -> (-1.1911, 10.6867)
  arc A19 (-1.6096, 10.1375) -> (-1.1911, 10.6867) centre (-1.688, 10.6313) ccw
  arc A20 (-1.6096, 10.1375) -> (-2.3924, 9.9818) centre (0, 0) ccw
  arc A21 (-2.9892, 10.329) -> (-2.3924, 9.9818) centre (-2.5089, 10.468) ccw
  line L10 (-2.9892, 10.329) -> (-3.1347, 10.8318)
  spline S10 degree 5 poles (-3.1347, 10.8318) (-3.1365, 10.8381) (-3.1404, 10.8506) (-3.1466, 10.8692) (-3.1559, 10.8936) (-3.169, 10.9236) (-3.183, 10.9533) (-3.1976, 10.9827) (-3.2126, 11.0121) (-3.2279, 11.0414) (-3.2433, 11.0706) (-3.2591, 11.0997) (-3.2753, 11.1286) (-3.2919, 11.1574) (-3.3091, 11.186) (-3.3267, 11.2144) (-3.3446, 11.2427) (-3.3629, 11.2708) (-3.3815, 11.2989) (-3.4003, 11.3268) (-3.4194, 11.3546) (-3.4388, 11.3823) (-3.4585, 11.4099) (-3.4784, 11.4374) (-3.4987, 11.4647) (-3.5193, 11.4919) (-3.5401, 11.519) (-3.5611, 11.546) (-3.5825, 11.5728) (-3.604, 11.5996) (-3.6258, 11.6262) (-3.6479, 11.6528) (-3.6701, 11.6792) (-3.6926, 11.7055) (-3.7154, 11.7317) (-3.7384, 11.7578) (-3.7616, 11.7837) (-3.785, 11.8096) (-3.8086, 11.8353) (-3.8325, 11.861) (-3.8566, 11.8865) (-3.8809, 11.9119) (-3.9054, 11.9372) (-3.93, 11.9624) (-3.955, 11.9875) (-3.9801, 12.0125) (-4.0054, 12.0374) (-4.0309, 12.0621) (-4.0566, 12.0868) (-4.0825, 12.1113) (-4.1085, 12.1357) (-4.1348, 12.16) (-4.1613, 12.1843) (-4.1879, 12.2083) (-4.2148, 12.2323) (-4.2418, 12.2562) (-4.269, 12.28) (-4.2964, 12.3036) (-4.3239, 12.3272) (-4.3517, 12.3506) (-4.3796, 12.3739) (-4.4077, 12.3971) (-4.4359, 12.4202) (-4.4644, 12.4432) (-4.493, 12.4661) (-4.5218, 12.4889) (-4.5507, 12.5115) (-4.5798, 12.5341) (-4.6091, 12.5565) (-4.6385, 12.5788) (-4.6681, 12.601) (-4.692, 12.6187) (-4.7099, 12.6319) (-4.7219, 12.6407) (-4.7279, 12.645) knots 0 0 0 0 0 0 0.01428571 0.02857143 0.04285714 0.05714286 0.07142857 0.08571429 0.1 0.11428571 0.12857143 0.14285714 0.15714286 0.17142857 0.18571429 0.2 0.21428571 0.22857143 0.24285714 0.25714286 0.27142857 0.28571429 0.3 0.31428571 0.32857143 0.34285714 0.35714286 0.37142857 0.38571429 0.4 0.41428571 0.42857143 0.44285714 0.45714286 0.47142857 0.48571429 0.5 0.51428571 0.52857143 0.54285714 0.55714286 0.57142857 0.58571429 0.6 0.61428571 0.62857143 0.64285714 0.65714286 0.67142857 0.68571429 0.7 0.71428571 0.72857143 0.74285714 0.75714286 0.77142857 0.78571429 0.8 0.81428571 0.82857143 0.84285714 0.85714286 0.87142857 0.88571429 0.9 0.91428571 0.92857143 0.94285714 0.95714286 0.97142857 0.98571429 1 1 1 1 1 1
  arc A22 (-4.7279, 12.645) -> (-5.5983, 12.2845) centre (0, 0) ccw
  spline S11 degree 5 poles (-5.5983, 12.2845) (-5.5994, 12.2772) (-5.6017, 12.2625) (-5.605, 12.2405) (-5.6094, 12.2111) (-5.6146, 12.1745) (-5.6197, 12.1379) (-5.6245, 12.1013) (-5.6291, 12.0648) (-5.6336, 12.0283) (-5.6378, 11.9919) (-5.6419, 11.9555) (-5.6457, 11.9191) (-5.6494, 11.8828) (-5.6529, 11.8465) (-5.6561, 11.8103) (-5.6591, 11.7741) (-5.662, 11.738) (-5.6646, 11.7019) (-5.6671, 11.6659) (-5.6693, 11.6299) (-5.6713, 11.5939) (-5.6731, 11.558) (-5.6747, 11.5222) (-5.6761, 11.4864) (-5.6772, 11.4507) (-5.6782, 11.4151) (-5.6789, 11.3795) (-5.6795, 11.3439) (-5.6798, 11.3084) (-5.6799, 11.273) (-5.6797, 11.2377) (-5.6794, 11.2024) (-5.6788, 11.1672) (-5.678, 11.132) (-5.677, 11.097) (-5.6757, 11.062) (-5.6742, 11.027) (-5.6725, 10.9922) (-5.6706, 10.9574) (-5.6684, 10.9227) (-5.6659, 10.8881) (-5.6633, 10.8536) (-5.6603, 10.8192) (-5.6571, 10.7848) (-5.6537, 10.7506) (-5.6501, 10.7164) (-5.6461, 10.6823) (-5.642, 10.6484) (-5.6375, 10.6145) (-5.6328, 10.5807) (-5.6278, 10.5471) (-5.6225, 10.5135) (-5.6169, 10.4801) (-5.611, 10.4468) (-5.6049, 10.4137) (-5.5984, 10.3806) (-5.5917, 10.3476) (-5.5848, 10.3148) (-5.5775, 10.2821) (-5.5698, 10.2496) (-5.5617, 10.2172) (-5.5532, 10.1851) (-5.5441, 10.1532) (-5.5347, 10.1215) (-5.525, 10.0899) (-5.515, 10.0584) (-5.5049, 10.027) (-5.4944, 9.9958) (-5.4833, 9.9649) (-5.4713, 9.9345) (-5.4607, 9.9106) (-5.452, 9.8931) (-5.4458, 9.8816) (-5.4427, 9.8759) knots -1 -1 -1 -1 -1 -1 -0.98571429 -0.97142857 -0.95714286 -0.94285714 -0.92857143 -0.91428571 -0.9 -0.88571429 -0.87142857 -0.85714286 -0.84285714 -0.82857143 -0.81428571 -0.8 -0.78571429 -0.77142857 -0.75714286 -0.74285714 -0.72857143 -0.71428571 -0.7 -0.68571429 -0.67142857 -0.65714286 -0.64285714 -0.62857143 -0.61428571 -0.6 -0.58571429 -0.57142857 -0.55714286 -0.54285714 -0.52857143 -0.51428571 -0.5 -0.48571429 -0.47142857 -0.45714286 -0.44285714 -0.42857143 -0.41428571 -0.4 -0.38571429 -0.37142857 -0.35714286 -0.34285714 -0.32857143 -0.31428571 -0.3 -0.28571429 -0.27142857 -0.25714286 -0.24285714 -0.22857143 -0.21428571 -0.2 -0.18571429 -0.17142857 -0.15714286 -0.14285714 -0.12857143 -0.11428571 -0.1 -0.08571429 -0.07142857 -0.05714286 -0.04285714 -0.02857143 -0.01428571 0 0 0 0 0 0
  line L11 (-5.4427, 9.8759) -> (-5.19, 9.4174)
  arc A23 (-5.3665, 8.7499) -> (-5.19, 9.4174) centre (-5.6279, 9.1761) ccw
  arc A24 (-5.3665, 8.7499) -> (-6.0302, 8.3065) centre (0, 0) ccw
  arc A25 (-6.7144, 8.3989) -> (-6.0302, 8.3065) centre (-6.3239, 8.7111) ccw
  line L12 (-6.7144, 8.3989) -> (-7.0413, 8.8077)
  spline S12 degree 5 poles (-7.0413, 8.8077) (-7.0454, 8.8128) (-7.0537, 8.8229) (-7.0665, 8.8377) (-7.0845, 8.8566) (-7.108, 8.8794) (-7.1323, 8.9014) (-7.1571, 8.923) (-7.1822, 8.9444) (-7.2075, 8.9656) (-7.233, 8.9867) (-7.2587, 9.0076) (-7.2847, 9.0281) (-7.3111, 9.0483) (-7.3379, 9.0682) (-7.365, 9.0877) (-7.3924, 9.107) (-7.4201, 9.126) (-7.448, 9.1448) (-7.4761, 9.1634) (-7.5044, 9.1817) (-7.5329, 9.1999) (-7.5616, 9.2179) (-7.5906, 9.2356) (-7.6197, 9.2531) (-7.6491, 9.2704) (-7.6787, 9.2874) (-7.7085, 9.3043) (-7.7385, 9.321) (-7.7687, 9.3374) (-7.799, 9.3537) (-7.8295, 9.3698) (-7.8602, 9.3857) (-7.8911, 9.4013) (-7.9221, 9.4168) (-7.9533, 9.4321) (-7.9847, 9.4473) (-8.0162, 9.4622) (-8.0479, 9.4769) (-8.0798, 9.4915) (-8.1118, 9.5058) (-8.1439, 9.52) (-8.1763, 9.534) (-8.2087, 9.5479) (-8.2413, 9.5615) (-8.2741, 9.575) (-8.307, 9.5883) (-8.34, 9.6014) (-8.3732, 9.6143) (-8.4065, 9.6271) (-8.4399, 9.6397) (-8.4735, 9.6521) (-8.5072, 9.6643) (-8.5411, 9.6764) (-8.5751, 9.6883) (-8.6092, 9.7) (-8.6434, 9.7115) (-8.6777, 9.7229) (-8.7122, 9.7341) (-8.7468, 9.7452) (-8.7815, 9.756) (-8.8164, 9.7667) (-8.8513, 9.7772) (-8.8864, 9.7876) (-8.9216, 9.7978) (-8.9569, 9.8078) (-8.9923, 9.8177) (-9.0278, 9.8273) (-9.0634, 9.8369) (-9.0992, 9.8462) (-9.135, 9.8554) (-9.1638, 9.8626) (-9.1854, 9.8679) (-9.1998, 9.8715) (-9.207, 9.8732) knots 0 0 0 0 0 0 0.01428571 0.02857143 0.04285714 0.05714286 0.07142857 0.08571429 0.1 0.11428571 0.12857143 0.14285714 0.15714286 0.17142857 0.18571429 0.2 0.21428571 0.22857143 0.24285714 0.25714286 0.27142857 0.28571429 0.3 0.31428571 0.32857143 0.34285714 0.35714286 0.37142857 0.38571429 0.4 0.41428571 0.42857143 0.44285714 0.45714286 0.47142857 0.48571429 0.5 0.51428571 0.52857143 0.54285714 0.55714286 0.57142857 0.58571429 0.6 0.61428571 0.62857143 0.64285714 0.65714286 0.67142857 0.68571429 0.7 0.71428571 0.72857143 0.74285714 0.75714286 0.77142857 0.78571429 0.8 0.81428571 0.82857143 0.84285714 0.85714286 0.87142857 0.88571429 0.9 0.91428571 0.92857143 0.94285714 0.95714286 0.97142857 0.98571429 1 1 1 1 1 1
  arc A26 (-9.207, 9.8732) -> (-9.8732, 9.207) centre (0, 0) ccw
  spline S13 degree 5 poles (-9.8732, 9.207) (-9.8715, 9.1998) (-9.8679, 9.1854) (-9.8626, 9.1638) (-9.8554, 9.135) (-9.8462, 9.0992) (-9.8369, 9.0634) (-9.8273, 9.0278) (-9.8177, 8.9923) (-9.8078, 8.9569) (-9.7978, 8.9216) (-9.7876, 8.8864) (-9.7772, 8.8513) (-9.7667, 8.8164) (-9.756, 8.7815) (-9.7452, 8.7468) (-9.7341, 8.7122) (-9.7229, 8.6777) (-9.7115, 8.6434) (-9.7, 8.6092) (-9.6883, 8.5751) (-9.6764, 8.5411) (-9.6643, 8.5072) (-9.6521, 8.4735) (-9.6397, 8.4399) (-9.6271, 8.4065) (-9.6143, 8.3732) (-9.6014, 8.34) (-9.5883, 8.307) (-9.575, 8.2741) (-9.5615, 8.2413) (-9.5479, 8.2087) (-9.534, 8.1763) (-9.52, 8.1439) (-9.5058, 8.1118) (-9.4915, 8.0798) (-9.4769, 8.0479) (-9.4622, 8.0162) (-9.4473, 7.9847) (-9.4321, 7.9533) (-9.4168, 7.9221) (-9.4013, 7.8911) (-9.3857, 7.8602) (-9.3698, 7.8295) (-9.3537, 7.799) (-9.3374, 7.7687) (-9.321, 7.7385) (-9.3043, 7.7085) (-9.2874, 7.6787) (-9.2704, 7.6491) (-9.2531, 7.6197) (-9.2356, 7.5906) (-9.2179, 7.5616) (-9.1999, 7.5329) (-9.1817, 7.5044) (-9.1634, 7.4761) (-9.1448, 7.448) (-9.126, 7.4201) (-9.107, 7.3924) (-9.0877, 7.365) (-9.0682, 7.3379) (-9.0483, 7.3111) (-9.0281, 7.2847) (-9.0076, 7.2587) (-8.9867, 7.233) (-8.9656, 7.2075) (-8.9444, 7.1822) (-8.923, 7.1571) (-8.9014, 7.1323) (-8.8794, 7.108) (-8.8566, 7.0845) (-8.8377, 7.0665) (-8.8229, 7.0537) (-8.8128, 7.0454) (-8.8077, 7.0413) knots -1 -1 -1 -1 -1 -1 -0.98571429 -0.97142857 -0.95714286 -0.94285714 -0.92857143 -0.91428571 -0.9 -0.88571429 -0.87142857 -0.85714286 -0.84285714 -0.82857143 -0.81428571 -0.8 -0.78571429 -0.77142857 -0.75714286 -0.74285714 -0.72857143 -0.71428571 -0.7 -0.68571429 -0.67142857 -0.65714286 -0.64285714 -0.62857143 -0.61428571 -0.6 -0.58571429 -0.57142857 -0.55714286 -0.54285714 -0.52857143 -0.51428571 -0.5 -0.48571429 -0.47142857 -0.45714286 -0.44285714 -0.42857143 -0.41428571 -0.4 -0.38571429 -0.37142857 -0.35714286 -0.34285714 -0.32857143 -0.31428571 -0.3 -0.28571429 -0.27142857 -0.25714286 -0.24285714 -0.22857143 -0.21428571 -0.2 -0.18571429 -0.17142857 -0.15714286 -0.14285714 -0.12857143 -0.11428571 -0.1 -0.08571429 -0.07142857 -0.05714286 -0.04285714 -0.02857143 -0.01428571 0 0 0 0 0 0
  line L13 (-8.8077, 7.0413) -> (-8.3989, 6.7144)
  arc A27 (-8.3065, 6.0302) -> (-8.3989, 6.7144) centre (-8.7111, 6.3239) ccw
  arc A28 (-8.3065, 6.0302) -> (-8.7499, 5.3665) centre (0, 0) ccw
  arc A29 (-9.4174, 5.19) -> (-8.7499, 5.3665) centre (-9.1761, 5.6279) ccw
  line L14 (-9.4174, 5.19) -> (-9.8759, 5.4427)
  spline S14 degree 5 poles (-9.8759, 5.4427) (-9.8816, 5.4458) (-9.8931, 5.452) (-9.9106, 5.4607) (-9.9345, 5.4713) (-9.9649, 5.4833) (-9.9958, 5.4944) (-10.027, 5.5049) (-10.0584, 5.515) (-10.0899, 5.525) (-10.1215, 5.5347) (-10.1532, 5.5441) (-10.1851, 5.5532) (-10.2172, 5.5617) (-10.2496, 5.5698) (-10.2821, 5.5775) (-10.3148, 5.5848) (-10.3476, 5.5917) (-10.3806, 5.5984) (-10.4137, 5.6049) (-10.4468, 5.611) (-10.4801, 5.6169) (-10.5135, 5.6225) (-10.5471, 5.6278) (-10.5807, 5.6328) (-10.6145, 5.6375) (-10.6484, 5.642) (-10.6823, 5.6461) (-10.7164, 5.6501) (-10.7506, 5.6537) (-10.7848, 5.6571) (-10.8192, 5.6603) (-10.8536, 5.6633) (-10.8881, 5.6659) (-10.9227, 5.6684) (-10.9574, 5.6706) (-10.9922, 5.6725) (-11.027, 5.6742) (-11.062, 5.6757) (-11.097, 5.677) (-11.132, 5.678) (-11.1672, 5.6788) (-11.2024, 5.6794) (-11.2377, 5.6797) (-11.273, 5.6799) (-11.3084, 5.6798) (-11.3439, 5.6795) (-11.3795, 5.6789) (-11.4151, 5.6782) (-11.4507, 5.6772) (-11.4864, 5.6761) (-11.5222, 5.6747) (-11.558, 5.6731) (-11.5939, 5.6713) (-11.6299, 5.6693) (-11.6659, 5.6671) (-11.7019, 5.6646) (-11.738, 5.662) (-11.7741, 5.6591) (-11.8103, 5.6561) (-11.8465, 5.6529) (-11.8828, 5.6494) (-11.9191, 5.6457) (-11.9555, 5.6419) (-11.9919, 5.6378) (-12.0283, 5.6336) (-12.0648, 5.6291) (-12.1013, 5.6245) (-12.1379, 5.6197) (-12.1745, 5.6146) (-12.2111, 5.6094) (-12.2405, 5.605) (-12.2625, 5.6017) (-12.2772, 5.5994) (-12.2845, 5.5983) knots 0 0 0 0 0 0 0.01428571 0.02857143 0.04285714 0.05714286 0.07142857 0.08571429 0.1 0.11428571 0.12857143 0.14285714 0.15714286 0.17142857 0.18571429 0.2 0.21428571 0.22857143 0.24285714 0.25714286 0.27142857 0.28571429 0.3 0.31428571 0.32857143 0.34285714 0.35714286 0.37142857 0.38571429 0.4 0.41428571 0.42857143 0.44285714 0.45714286 0.47142857 0.48571429 0.5 0.51428571 0.52857143 0.54285714 0.55714286 0.57142857 0.58571429 0.6 0.61428571 0.62857143 0.64285714 0.65714286 0.67142857 0.68571429 0.7 0.71428571 0.72857143 0.74285714 0.75714286 0.77142857 0.78571429 0.8 0.81428571 0.82857143 0.84285714 0.85714286 0.87142857 0.88571429 0.9 0.91428571 0.92857143 0.94285714 0.95714286 0.97142857 0.98571429 1 1 1 1 1 1
  arc A30 (-12.2845, 5.5983) -> (-12.645, 4.7279) centre (0, 0) ccw
  spline S15 degree 5 poles (-12.645, 4.7279) (-12.6407, 4.7219) (-12.6319, 4.7099) (-12.6187, 4.692) (-12.601, 4.6681) (-12.5788, 4.6385) (-12.5565, 4.6091) (-12.5341, 4.5798) (-12.5115, 4.5507) (-12.4889, 4.5218) (-12.4661, 4.493) (-12.4432, 4.4644) (-12.4202, 4.4359) (-12.3971, 4.4077) (-12.3739, 4.3796) (-12.3506, 4.3517) (-12.3272, 4.3239) (-12.3036, 4.2964) (-12.28, 4.269) (-12.2562, 4.2418) (-12.2323, 4.2148) (-12.2083, 4.1879) (-12.1843, 4.1613) (-12.16, 4.1348) (-12.1357, 4.1085) (-12.1113, 4.0825) (-12.0868, 4.0566) (-12.0621, 4.0309) (-12.0374, 4.0054) (-12.0125, 3.9801) (-11.9875, 3.955) (-11.9624, 3.93) (-11.9372, 3.9054) (-11.9119, 3.8809) (-11.8865, 3.8566) (-11.861, 3.8325) (-11.8353, 3.8086) (-11.8096, 3.785) (-11.7837, 3.7616) (-11.7578, 3.7384) (-11.7317, 3.7154) (-11.7055, 3.6926) (-11.6792, 3.6701) (-11.6528, 3.6479) (-11.6262, 3.6258) (-11.5996, 3.604) (-11.5728, 3.5825) (-11.546, 3.5611) (-11.519, 3.5401) (-11.4919, 3.5193) (-11.4647, 3.4987) (-11.4374, 3.4784) (-11.4099, 3.4585) (-11.3823, 3.4388) (-11.3546, 3.4194) (-11.3268, 3.4003) (-11.2989, 3.3815) (-11.2708, 3.3629) (-11.2427, 3.3446) (-11.2144, 3.3267) (-11.186, 3.3091) (-11.1574, 3.2919) (-11.1286, 3.2753) (-11.0997, 3.2591) (-11.0706, 3.2433) (-11.0414, 3.2279) (-11.0121, 3.2126) (-10.9827, 3.1976) (-10.9533, 3.183) (-10.9236, 3.169) (-10.8936, 3.1559) (-10.8692, 3.1466) (-10.8506, 3.1404) (-10.8381, 3.1365) (-10.8318, 3.1347) knots -1 -1 -1 -1 -1 -1 -0.98571429 -0.97142857 -0.95714286 -0.94285714 -0.92857143 -0.91428571 -0.9 -0.88571429 -0.87142857 -0.85714286 -0.84285714 -0.82857143 -0.81428571 -0.8 -0.78571429 -0.77142857 -0.75714286 -0.74285714 -0.72857143 -0.71428571 -0.7 -0.68571429 -0.67142857 -0.65714286 -0.64285714 -0.62857143 -0.61428571 -0.6 -0.58571429 -0.57142857 -0.55714286 -0.54285714 -0.52857143 -0.51428571 -0.5 -0.48571429 -0.47142857 -0.45714286 -0.44285714 -0.42857143 -0.41428571 -0.4 -0.38571429 -0.37142857 -0.35714286 -0.34285714 -0.32857143 -0.31428571 -0.3 -0.28571429 -0.27142857 -0.25714286 -0.24285714 -0.22857143 -0.21428571 -0.2 -0.18571429 -0.17142857 -0.15714286 -0.14285714 -0.12857143 -0.11428571 -0.1 -0.08571429 -0.07142857 -0.05714286 -0.04285714 -0.02857143 -0.01428571 0 0 0 0 0 0
  line L15 (-10.8318, 3.1347) -> (-10.329, 2.9892)
  arc A31 (-9.9818, 2.3924) -> (-10.329, 2.9892) centre (-10.468, 2.5089) ccw
  arc A32 (-9.9818, 2.3924) -> (-10.1375, 1.6096) centre (0, 0) ccw
  arc A33 (-10.6867, 1.1911) -> (-10.1375, 1.6096) centre (-10.6313, 1.688) ccw
  line L16 (-10.6867, 1.1911) -> (-11.2069, 1.2491)
  spline S16 degree 5 poles (-11.2069, 1.2491) (-11.2134, 1.2498) (-11.2264, 1.251) (-11.246, 1.2524) (-11.2721, 1.2531) (-11.3048, 1.2525) (-11.3376, 1.2509) (-11.3704, 1.2487) (-11.4033, 1.2461) (-11.4361, 1.2432) (-11.469, 1.2401) (-11.502, 1.2367) (-11.5349, 1.2328) (-11.5679, 1.2284) (-11.6008, 1.2235) (-11.6338, 1.2181) (-11.6668, 1.2124) (-11.6998, 1.2062) (-11.7328, 1.1998) (-11.7659, 1.1931) (-11.7989, 1.1861) (-11.8319, 1.1788) (-11.8649, 1.1712) (-11.8979, 1.1632) (-11.9309, 1.155) (-11.9639, 1.1464) (-11.9969, 1.1375) (-12.0299, 1.1284) (-12.0629, 1.119) (-12.0958, 1.1093) (-12.1288, 1.0993) (-12.1617, 1.0891) (-12.1947, 1.0787) (-12.2276, 1.0679) (-12.2605, 1.0569) (-12.2934, 1.0457) (-12.3262, 1.0342) (-12.3591, 1.0224) (-12.3919, 1.0105) (-12.4247, 0.9982) (-12.4575, 0.9858) (-12.4903, 0.973) (-12.5231, 0.9601) (-12.5558, 0.9469) (-12.5885, 0.9335) (-12.6212, 0.9199) (-12.6539, 0.906) (-12.6865, 0.8919) (-12.7191, 0.8776) (-12.7517, 0.8631) (-12.7842, 0.8483) (-12.8167, 0.8334) (-12.8492, 0.8182) (-12.8817, 0.8028) (-12.9141, 0.7872) (-12.9465, 0.7713) (-12.9789, 0.7553) (-13.0112, 0.7391) (-13.0435, 0.7226) (-13.0758, 0.7059) (-13.108, 0.6891) (-13.1402, 0.672) (-13.1724, 0.6547) (-13.2045, 0.6373) (-13.2366, 0.6196) (-13.2686, 0.6017) (-13.3006, 0.5836) (-13.3326, 0.5654) (-13.3645, 0.5469) (-13.3964, 0.5282) (-13.4282, 0.5094) (-13.4537, 0.4942) (-13.4727, 0.4826) (-13.4854, 0.4749) (-13.4918, 0.4711) knots 0 0 0 0 0 0 0.01428571 0.02857143 0.04285714 0.05714286 0.07142857 0.08571429 0.1 0.11428571 0.12857143 0.14285714 0.15714286 0.17142857 0.18571429 0.2 0.21428571 0.22857143 0.24285714 0.25714286 0.27142857 0.28571429 0.3 0.31428571 0.32857143 0.34285714 0.35714286 0.37142857 0.38571429 0.4 0.41428571 0.42857143 0.44285714 0.45714286 0.47142857 0.48571429 0.5 0.51428571 0.52857143 0.54285714 0.55714286 0.57142857 0.58571429 0.6 0.61428571 0.62857143 0.64285714 0.65714286 0.67142857 0.68571429 0.7 0.71428571 0.72857143 0.74285714 0.75714286 0.77142857 0.78571429 0.8 0.81428571 0.82857143 0.84285714 0.85714286 0.87142857 0.88571429 0.9 0.91428571 0.92857143 0.94285714 0.95714286 0.97142857 0.98571429 1 1 1 1 1 1
  arc A34 (-13.4918, 0.4711) -> (-13.4918, -0.4711) centre (0, 0) ccw
  spline S17 degree 5 poles (-13.4918, -0.4711) (-13.4854, -0.4749) (-13.4727, -0.4826) (-13.4537, -0.4942) (-13.4282, -0.5094) (-13.3964, -0.5282) (-13.3645, -0.5469) (-13.3326, -0.5654) (-13.3006, -0.5836) (-13.2686, -0.6017) (-13.2366, -0.6196) (-13.2045, -0.6373) (-13.1724, -0.6547) (-13.1402, -0.672) (-13.108, -0.6891) (-13.0758, -0.7059) (-13.0435, -0.7226) (-13.0112, -0.7391) (-12.9789, -0.7553) (-12.9465, -0.7713) (-12.9141, -0.7872) (-12.8817, -0.8028) (-12.8492, -0.8182) (-12.8167, -0.8334) (-12.7842, -0.8483) (-12.7517, -0.8631) (-12.7191, -0.8776) (-12.6865, -0.8919) (-12.6539, -0.906) (-12.6212, -0.9199) (-12.5885, -0.9335) (-12.5558, -0.9469) (-12.5231, -0.9601) (-12.4903, -0.973) (-12.4575, -0.9858) (-12.4247, -0.9982) (-12.3919, -1.0105) (-12.3591, -1.0224) (-12.3262, -1.0342) (-12.2934, -1.0457) (-12.2605, -1.0569) (-12.2276, -1.0679) (-12.1947, -1.0787) (-12.1617, -1.0891) (-12.1288, -1.0993) (-12.0958, -1.1093) (-12.0629, -1.119) (-12.0299, -1.1284) (-11.9969, -1.1375) (-11.9639, -1.1464) (-11.9309, -1.155) (-11.8979, -1.1632) (-11.8649, -1.1712) (-11.8319, -1.1788) (-11.7989, -1.1861) (-11.7659, -1.1931) (-11.7328, -1.1998) (-11.6998, -1.2062) (-11.6668, -1.2124) (-11.6338, -1.2181) (-11.6008, -1.2235) (-11.5679, -1.2284) (-11.5349, -1.2328) (-11.502, -1.2367) (-11.469, -1.2401) (-11.4361, -1.2432) (-11.4033, -1.2461) (-11.3704, -1.2487) (-11.3376, -1.2509) (-11.3048, -1.2525) (-11.2721, -1.2531) (-11.246, -1.2524) (-11.2264, -1.251) (-11.2134, -1.2498) (-11.2069, -1.2491) knots -1 -1 -1 -1 -1 -1 -0.98571429 -0.97142857 -0.95714286 -0.94285714 -0.92857143 -0.91428571 -0.9 -0.88571429 -0.87142857 -0.85714286 -0.84285714 -0.82857143 -0.81428571 -0.8 -0.78571429 -0.77142857 -0.75714286 -0.74285714 -0.72857143 -0.71428571 -0.7 -0.68571429 -0.67142857 -0.65714286 -0.64285714 -0.62857143 -0.61428571 -0.6 -0.58571429 -0.57142857 -0.55714286 -0.54285714 -0.52857143 -0.51428571 -0.5 -0.48571429 -0.47142857 -0.45714286 -0.44285714 -0.42857143 -0.41428571 -0.4 -0.38571429 -0.37142857 -0.35714286 -0.34285714 -0.32857143 -0.31428571 -0.3 -0.28571429 -0.27142857 -0.25714286 -0.24285714 -0.22857143 -0.21428571 -0.2 -0.18571429 -0.17142857 -0.15714286 -0.14285714 -0.12857143 -0.11428571 -0.1 -0.08571429 -0.07142857 -0.05714286 -0.04285714 -0.02857143 -0.01428571 0 0 0 0 0 0
  line L17 (-11.2069, -1.2491) -> (-10.6867, -1.1911)
  arc A35 (-10.1375, -1.6096) -> (-10.6867, -1.1911) centre (-10.6313, -1.688) ccw
  arc A36 (-10.1375, -1.6096) -> (-9.9818, -2.3924) centre (0, 0) ccw
  arc A37 (-10.329, -2.9892) -> (-9.9818, -2.3924) centre (-10.468, -2.5089) ccw
  line L18 (-10.329, -2.9892) -> (-10.8318, -3.1347)